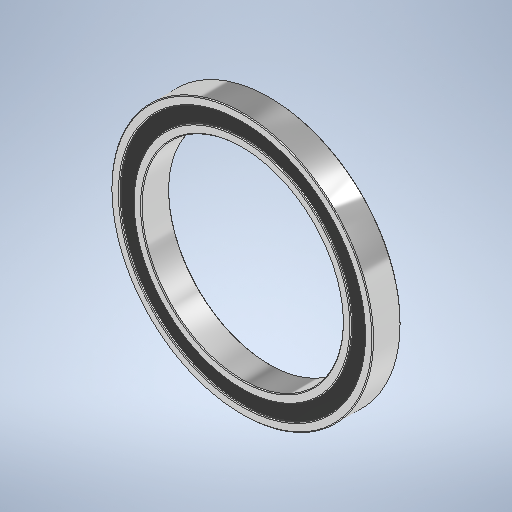
# Autodesk Inventor part: 6810ZZ
Saved by Autodesk Inventor 2025.3 (Build 293356030, 356C)
## iProperties
Created: 2026-02-11
Part Number: 6810ZZ
Material: 一般
Document SubType Name: Modeling
Designer: ibuki_ono
Density: 1 g/cm^3
Appearance: クロム - つや出し
Author: ibuki_ono
Autodesk Inventor part; units mm, degrees
ref_plane "YZ Plane" through (0, 0, 0) normal (1, 0, 0) x (0, 1, 0)
ref_plane "XZ Plane" through (0, 0, 0) normal (0, 1, 0) x (-1, 0, 0)
ref_plane "XY Plane" through (0, 0, 0) normal (0, 0, 1) x (1, 0, 0)
sketch "スケッチ1" plane through (0, 0, 0) normal (0, 0, 1) x (1, 0, 0)
  circle A0 centre (0, 0) radius 32.5
  circle A1 centre (0, 0) radius 25
  dimension "d0" = 65
  dimension "d1" = 50
  constraints: 2 centre point, 2 coincident
  measures "d0" diameter of A0
  measures "d1" diameter of A1
extrude "押し出し1" add sketch "スケッチ1" along normal mid plane 7
sketch "スケッチ2" plane through (0, 0, 3.5) normal (0, 0, 1) x (1, 0, 0)
  circle A0 centre (0, 0) radius 32.5 projected
  circle A1 centre (0, 0) radius 25 projected
  circle A2 centre (0, 0) radius 30.5
  circle A3 centre (0, 0) radius 27
  dimension "d4" = 2
  dimension "d5" = 2
  constraints: 2 centre point
  measures "d4" radial gap between concentric circles of A0 A2
  measures "d5" radial gap between concentric circles of A1 A3
extrude "押し出し2" cut sketch "スケッチ2" against normal blind 0.5 contours A2
mirror "ミラー1" about plane through (0, 0, 0) normal (0, 0, 1) of "押し出し2"
fillet "フィレット2" radius 0.2 8 edges at (-32.5, 0, -3.5) (-30.5, 0, -3.5) (-27, 0, -3.5) (-25, 0, -3.5) (-32.5, 0, 3.5) (-30.5, 0, 3.5) (-27, 0, 3.5) (-25, 0, 3.5)
equation "\"d5\" = d4"
